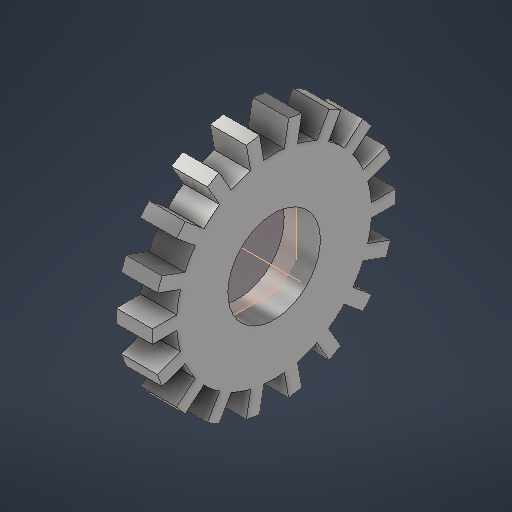
# Autodesk Inventor part: Cam_Sprocket_Secondary
Saved by Autodesk Inventor 2027.1 (Build 311270010, 270A)
## iProperties
Created: 2026-10-17
Part Number: Cam_Sprocket_Secondary
Material: Steel, Carbon
Document SubType Name: Modeling
Designer: kashyap
Density: 7.85 g/cm^3
Appearance: Semi-Polished
Material_Status: Assumed for this reconstruction
Author: kashyap
Autodesk Inventor part; units mm, degrees
derived "V6_Engine_Master.ipt"
ref_plane "Sprocket_Mid_Plane" through (0, 0, 0) normal (1, 0, 0) x (0, 1, 0)
sketch "SK_Root" plane through (0, 0, 0) normal (1, 0, 0) x (0, 1, 0)
  circle A0 centre (0, 0) radius 24.2543
  circle A1 centre (0, 0) radius 11.5
  dimension "d20" = 48.5086
  dimension "d21" = 23
  constraints: 2 centre point
  measures "d20" diameter of A0
  measures "d21" diameter of A1
extrude "Sprocket_Disc" add sketch "SK_Root" along normal mid plane 9
sketch "SK_Tooth" plane through (0, 0, 0) normal (1, 0, 0) x (0, 1, 0)
  line L0 (-1.6669, 23.2543) -> (1.6669, 23.2543)
  line L1 (1.6669, 23.2543) -> (1.6669, 30.2836)
  line L2 (1.6669, 30.2836) -> (-1.6669, 30.2836)
  line L3 (-1.6669, 30.2836) -> (-1.6669, 23.2543)
  constraints: 8 end point, 2 parallel, 1 horizontal, 1 perpendicular
extrude "Tooth_SIMPLIFIED" add sketch "SK_Tooth" along normal mid plane 9
pattern_circular "Teeth_Pattern" count 18 over 360 about axis through (0, 0, 0) along (-1, 0, 0) of "Tooth_SIMPLIFIED"
equation "\"d20\" = Secondary_Sprocket_PCD - 0.666 * Timing_Chain_Pitch"
equation "\"d21\" = Cam_Journal_Dia_Other"
equation "\"d22\" = Sprocket_Width"
equation "\"d24\" = Sprocket_Width"
equation "\"Secondary_Sprocket_PCD\" = 54.852289"
equation "\"Timing_Chain_Pitch\" = 9.525"
equation "\"Cam_Journal_Dia_Other\" = 23"
equation "\"Sprocket_Width\" = 9"
body "Solid1"
